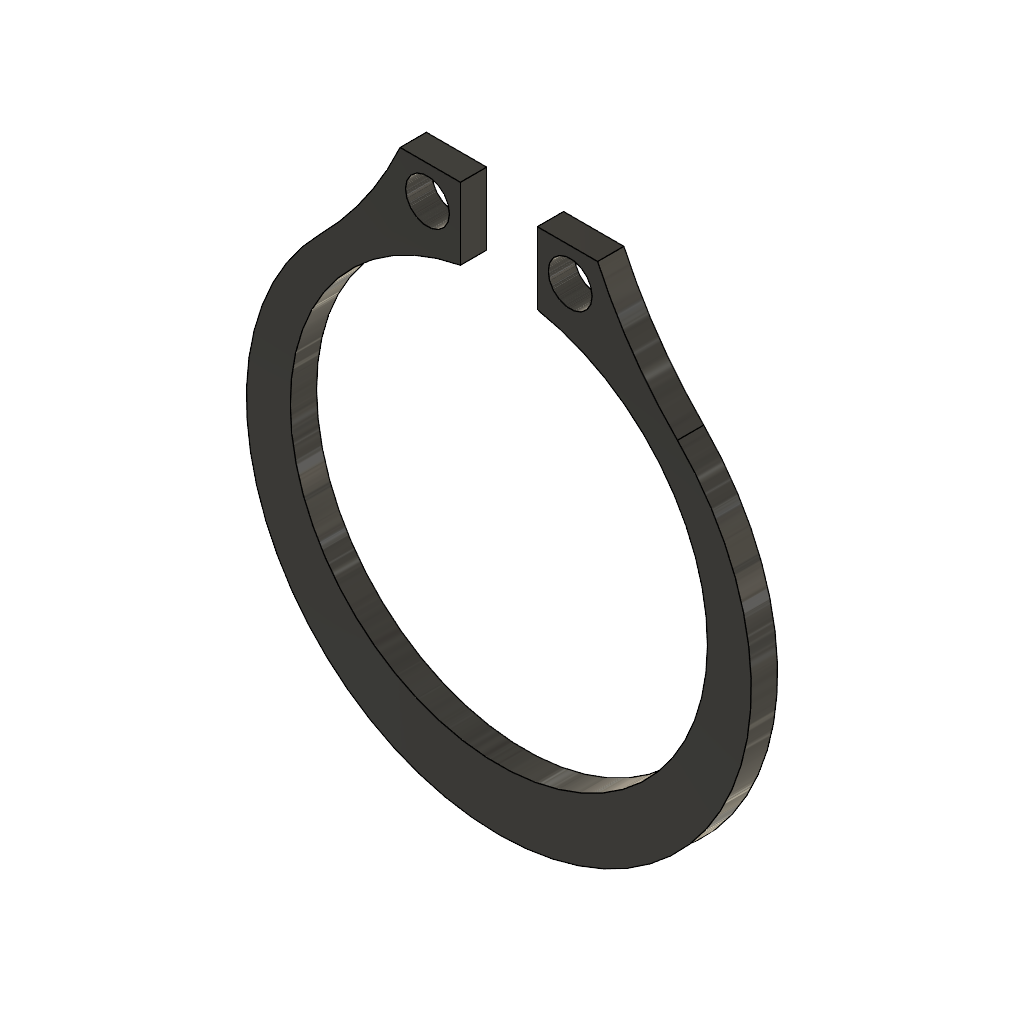
two_stage_reduction_v2 (Autodesk Fusion 360 archive; units mm, degrees)
design "counter_retaining_ring"
part number: 2026-10-06-01-37-24-822
Autodesk Fusion 360 part; units mm, degrees
sketch "Sketch1" plane through (0, 0, 0) normal (0, 1, 0) x (1, 0, 0)
  line L0 (0, 0) -> (0, -16.4292)
  line L1 (-1.75, -12.613) -> (-1.75, -9.3374)
  line L2 (-1.75, -12.613) -> (-4.5, -12.613)
  arc A0 (-4.5, -12.613) -> (-8.1353, -7.3782) centre (-20.8688, -20.1005) ccw
  arc A1 (8.1353, -7.3782) -> (4.5, -12.613) centre (20.8688, -20.1005) ccw
  line L3 (1.75, -12.613) -> (4.5, -12.613)
  line L4 (1.75, -12.613) -> (1.75, -9.3374)
  arc A2 (8.1353, -7.3782) -> (-8.1353, -7.3782) centre (0, 0.75) ccw
  arc A3 (1.75, -9.3374) -> (-1.75, -9.3374) centre (0, 0) ccw
  dimension "d1" = 19
  dimension "d2" = 0.75
  dimension "d3" = 23
  dimension "d5" = 3.5
  dimension "d6" = 9
  dimension "d7" = 18
  constraint coincident L0.start A3.centre
  constraint vertical L0
  constraint vertical L1
  constraint perpendicular L1 L2
  constraint tangent A0 A2
  constraint symmetric L0 L1.start L3.start
  constraint symmetric L0 L1.end L4.end
  constraint symmetric L0 L2.end A1.end
  constraint symmetric L0 A0.end A1.start
  constraint symmetric L0 A0 A1
  measures "d1" diameter of A3
  measures "d2" distance of L0.start A2.centre
  measures "d3" diameter of A2
  measures "d6" distance of L2.end A1.end
  measures "d7" radius of A0
extrude "Extrude1" add sketch "Sketch1" along normal blind 1.2
sketch "Sketch2" plane through (0, 0, 0) normal (0, 1, 0) x (1, 0, 0)
  circle A0 centre (-3.25, -11.113) radius 1
  line L0 (-1.75, -12.613) -> (-4.5, -12.613)
  line L1 (-1.75, -12.613) -> (-1.75, -9.3374)
  line L2 (0, -13.9274) -> (0, 0)
  circle A1 centre (3.25, -11.113) radius 1
  dimension "d10" = 2
  dimension "d11" = 1.5
  dimension "d12" = 1.5
  constraint coincident L2.end origin
  constraint vertical L2
  constraint symmetric A0 L2 A1
  measures "d10" diameter of A0
  measures "d11" distance of A0.centre L0
  measures "d12" distance of A0.centre L1
extrude "Extrude2" cut sketch "Sketch2" along normal blind 1.2

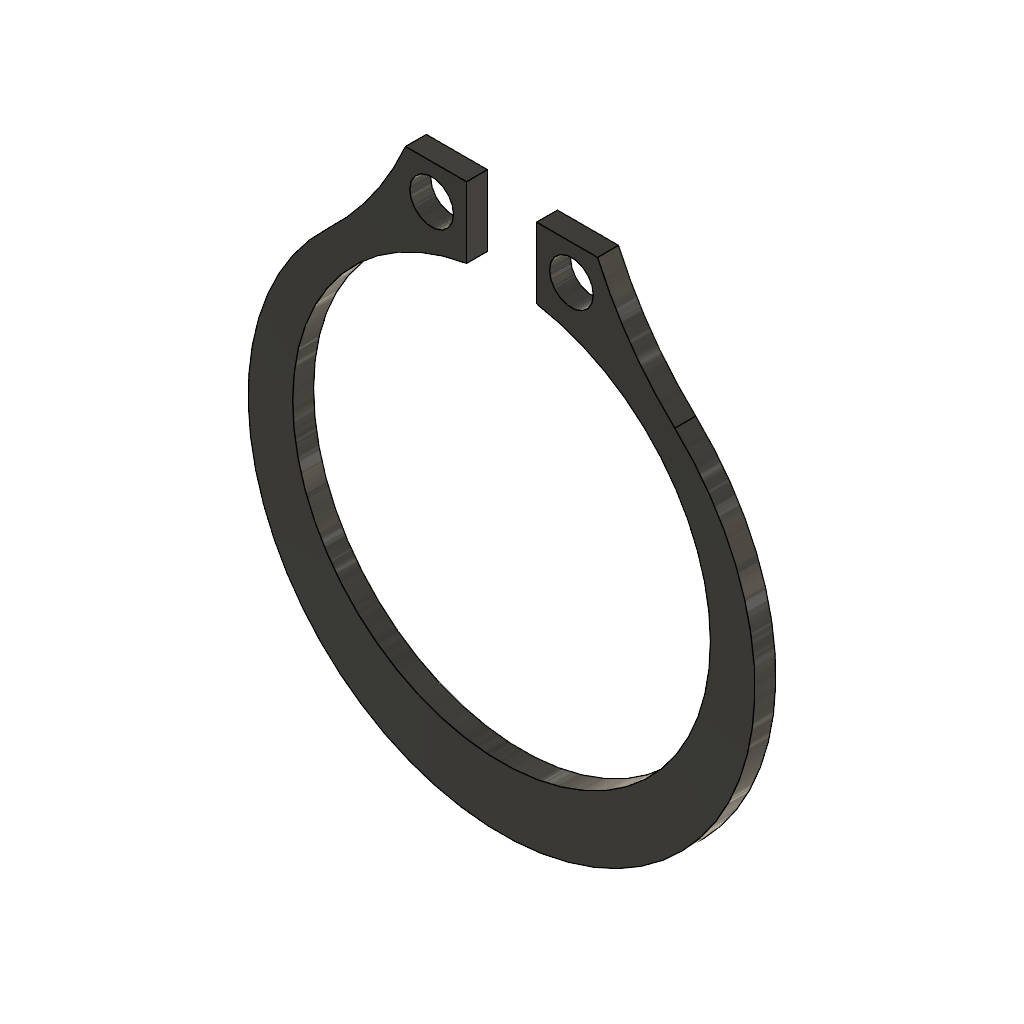
design "output_retaining_ring"
part number: 2026-10-06-01-58-45-962
Autodesk Fusion 360 part; units mm, degrees
sketch "Sketch1" plane through (0, 0, 0) normal (0, 1, 0) x (1, 0, 0)
  line L0 (0, 0) -> (0, -25)
  line L1 (-2, -15.834) -> (-2, -11.7814)
  line L2 (-2, -15.834) -> (-5.5, -15.834)
  arc A0 (-5.5, -15.834) -> (-9.9167, -9.5787) centre (-22.911, -23.4405) ccw
  arc A1 (9.9167, -9.5787) -> (5.5, -15.834) centre (22.911, -23.4405) ccw
  line L3 (2, -15.834) -> (5.5, -15.834)
  line L4 (2, -15.834) -> (2, -11.7814)
  arc A2 (9.9167, -9.5787) -> (-9.9167, -9.5787) centre (0, 1) ccw
  arc A3 (2, -11.7814) -> (-2, -11.7814) centre (0, 0) ccw
  dimension "d1" = 23.9
  dimension "d2" = 29
  dimension "d3" = 1
  dimension "d4" = 4
  dimension "d6" = 11
  dimension "d7" = 19
  constraint coincident L0.start A3.centre
  constraint vertical L0
  constraint vertical L1
  constraint perpendicular L1 L2
  constraint tangent A0 A2
  constraint symmetric L0 L1.start L3.start
  constraint symmetric L0 L1.end L4.end
  constraint symmetric L0 L2.end A1.end
  constraint symmetric L0 A0.end A1.start
  constraint symmetric L0 A0 A1
  measures "d1" diameter of A3
  measures "d2" diameter of A2
  measures "d3" distance of L0.start A2.centre
  measures "d6" distance of L2.end A1.end
  measures "d7" radius of A0
extrude "Extrude1" add sketch "Sketch1" along normal blind 1.2
sketch "Sketch2" plane through (0, 0, 0) normal (0, 1, 0) x (1, 0, 0)
  circle A0 centre (-4, -13.834) radius 1.25
  line L0 (-2, -15.834) -> (-5.5, -15.834)
  line L1 (-2, -15.834) -> (-2, -11.7814)
  line L2 (0, -17.5) -> (0, 0)
  circle A1 centre (4, -13.834) radius 1.25
  dimension "d10" = 2.5
  dimension "d11" = 2
  dimension "d12" = 2
  constraint coincident L2.end origin
  constraint vertical L2
  constraint symmetric A0 L2 A1
  measures "d10" diameter of A0
  measures "d11" distance of A0.centre L0
  measures "d12" distance of A0.centre L1
extrude "Extrude2" cut sketch "Sketch2" along normal blind 1.2

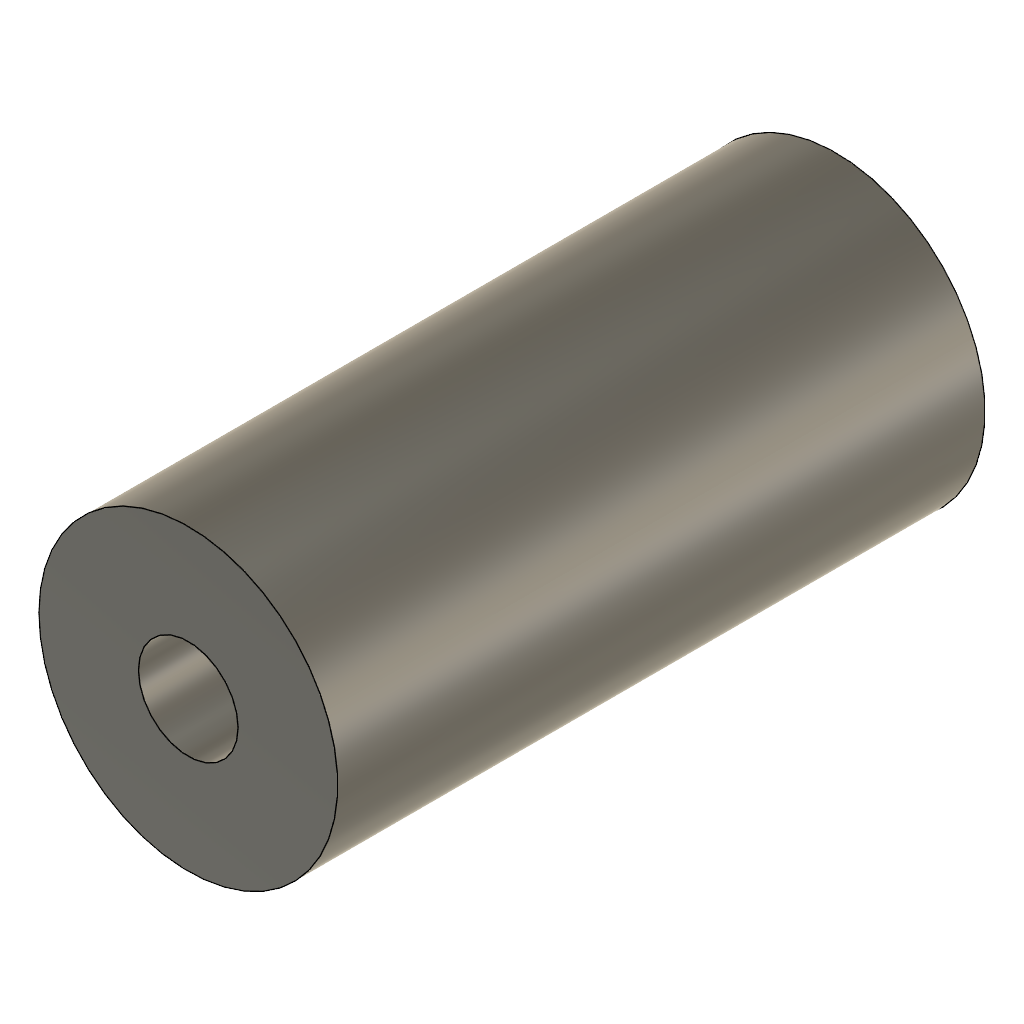
design "input_gearspacer"
part number: 2026-10-07-02-27-22-162
Autodesk Fusion 360 part; units mm, degrees
sketch "Sketch1" plane through (0, 0, 0) normal (0, 1, 0) x (1, 0, 0)
  circle A0 centre (0, 0) radius 5
  circle A1 centre (0, 0) radius 15
  dimension "d1" = 10
  dimension "d2" = 30
  constraint coincident A0.centre A1.centre
  constraint concentric A0 A1
  measures "d1" diameter of A0
  measures "d2" diameter of A1
extrude "Extrude1" add sketch "Sketch1" along normal blind 65

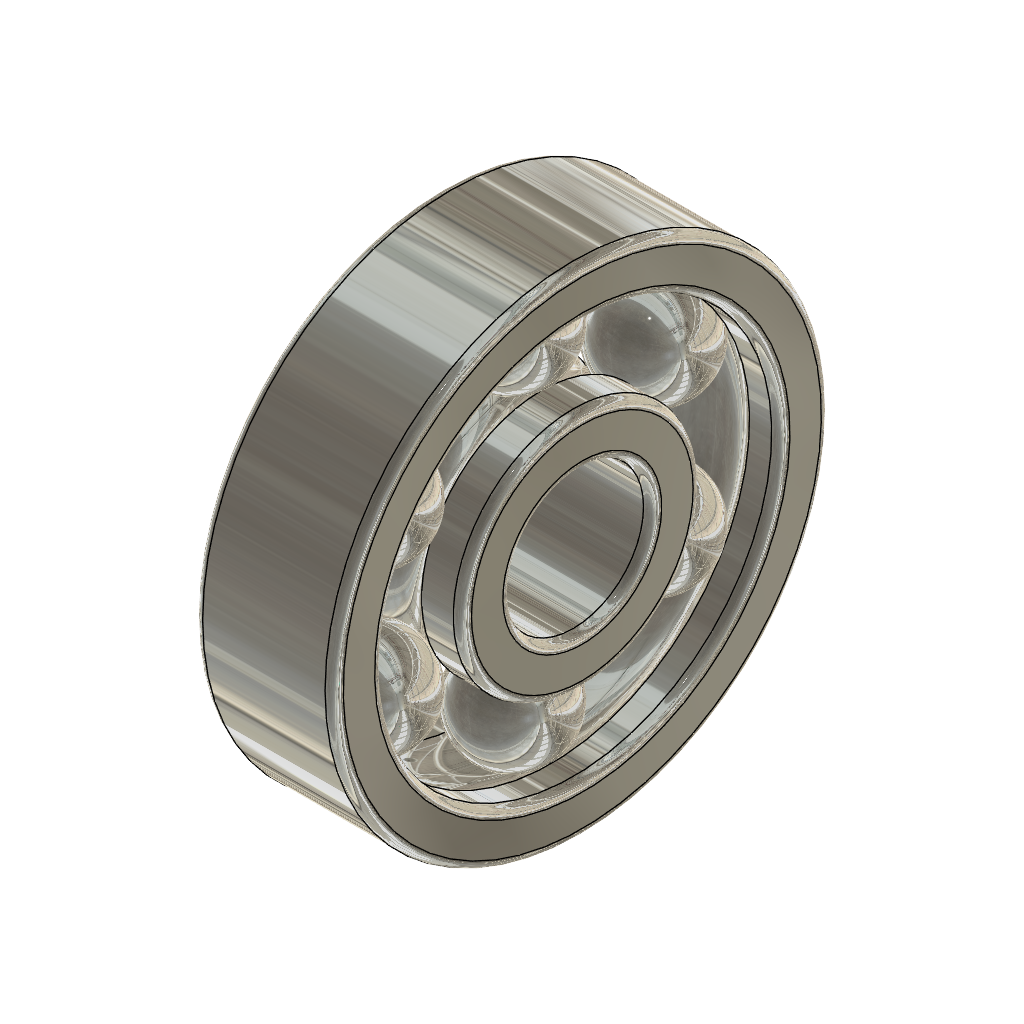
design "input_bearing"
part number: 2026-10-06-00-42-18-262
Autodesk Fusion 360 part; units mm, degrees
sketch "Sketch1" plane through (0, 0, 0) normal (0, 1, 0) x (1, 0, 0)
  line L0 (-8.5, -30) -> (8.5, -30)
  line L1 (8.5, -30) -> (8.5, -24)
  line L2 (-8.5, -24) -> (-8.5, -30)
  line L3 (8.5, -24) -> (4.7181, -24)
  line L4 (-4.7181, -24) -> (-8.5, -24)
  arc A0 (-4.7181, -24) -> (4.7181, -24) centre (0, -19.75) ccw
  dimension "d1" = 6
  dimension "d2" = 17
  dimension "d4" = 8.5
  dimension "d6" = 30
  dimension "d7" = 12.7
  dimension "d9" = 19.75
  constraint horizontal L0
  constraint vertical L1
  constraint horizontal L3
  constraint vertical L2
  constraint vertical origin A0.centre
  constraint collinear L3 L4
  measures "d1" distance of L0.start L2.start
  measures "d2" distance of L0.start L0.end
  measures "d4" distance of origin L1
  measures "d6" distance of origin L0
  measures "d7" diameter of A0
  measures "d9" distance of origin A0.centre
revolve "Revolve1" add sketch "Sketch1" angle 360 about axis through (1.75, 0, 0) along (1, 0, 0) makes body 1
sketch "Sketch2" plane through (0, 0, 0) normal (0, 1, 0) x (1, 0, 0)
  line L0 (8.5, -14.5) -> (8.5, -8.5)
  line L1 (8.5, -8.5) -> (-8.5, -8.5)
  line L2 (-8.5, -8.5) -> (-8.5, -14.5)
  arc A0 (3.5721, -14.5) -> (-3.5721, -14.5) centre (0, -19.75) ccw
  line L3 (-8.5, -14.5) -> (-3.5721, -14.5)
  line L4 (3.5721, -14.5) -> (8.5, -14.5)
  dimension "d13" = 17
  dimension "d14" = 6
  dimension "d15" = 8.5
  dimension "d16" = 12.7
  dimension "d17" = 19.75
  dimension "d29" = 8.5
  constraint horizontal L3
  constraint vertical L0
  constraint horizontal L1
  constraint vertical L2
  constraint collinear L3 L4
  measures "d13" distance of L2.end L0.start
  measures "d14" distance of L2.end L1.end
  measures "d15" distance of origin L0
  measures "d16" diameter of A0
  measures "d17" distance of origin A0.centre
  measures "d29" distance of origin L1
revolve "Revolve2" add sketch "Sketch2" angle 360 about axis through (1.75, 0, 0) along (1, 0, 0) separate body makes body 2
fillet "Fillet3" radius 1.1 4 faces at (-8.5, 1.4904, 27.8883) (8.5, 2.6828, 27.799) (8.5, 1.1427, 12.4144) (-8.5, 0.7204, 12.446) on bodies 1 2
sketch "Sketch3" plane through (0, 0, 0) normal (1, 0, 0) x (0, 1, 0)
  line L0 (0, 26.1) -> (0, 13.4)
  arc A0 (0, 26.1) -> (0, 13.4) centre (0, 19.75) ccw
  dimension "d23" = 12.7
  dimension "d25" = 19.75
  constraint perpendicular L0 A0
  measures "d23" diameter of A0
  measures "d25" distance of origin A0.centre
revolve "Revolve3" add sketch "Sketch3" angle 360 about axis through (0, 0, 26.1) along (0, 0, -1) separate body makes body 3
pattern_circular "C-Pattern1" count 6 over 360 about axis through (1.75, 0, 0) along (1, 0, 0) of bodies 3 makes body 4 at (-1.501, -21.2843, 5.3369) makes body 5 at (-1.501, -15.264, -15.7643) makes body 6 at (-1.501, 6.0203, -21.1012) makes body 7 at (-1.501, 21.2843, -5.3369) makes body 8 at (-1.501, 15.264, 15.7643)

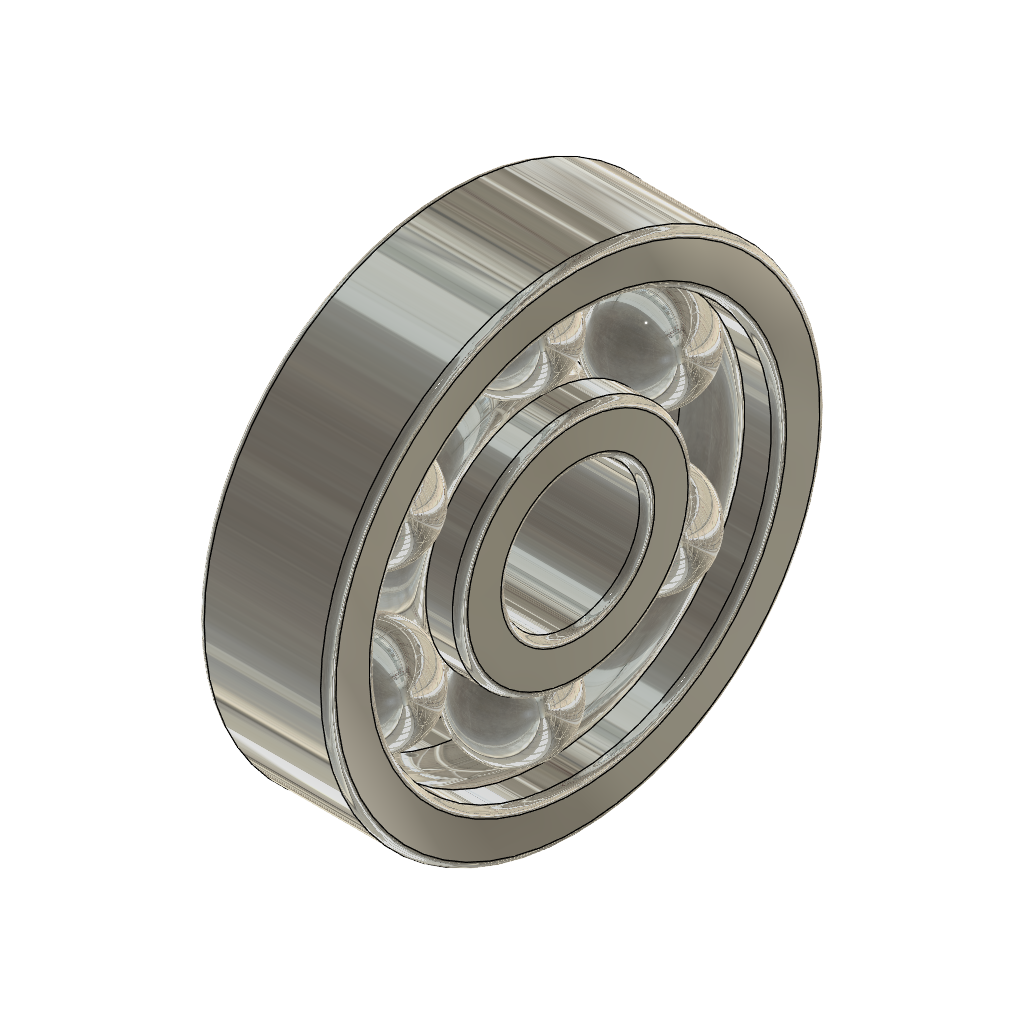
design "counter_bearing"
part number: 2026-10-06-02-07-17-765
Autodesk Fusion 360 part; units mm, degrees
sketch "Sketch1" plane through (0, 0, 0) normal (0, 1, 0) x (1, 0, 0)
  line L0 (-9.5, -29) -> (-9.5, -36)
  line L1 (-9.5, -36) -> (9.5, -36)
  line L2 (9.5, -36) -> (9.5, -29)
  line L3 (9.5, -29) -> (4.5622, -29)
  line L4 (-4.5622, -29) -> (-9.5, -29)
  arc A0 (-4.5622, -29) -> (4.5622, -29) centre (0, -23) ccw
  dimension "d1" = 19
  dimension "d2" = 7
  dimension "d4" = 9.5
  dimension "d5" = 36
  dimension "d6" = 15.075
  dimension "d7" = 23
  constraint horizontal L3
  constraint vertical L0
  constraint horizontal L1
  constraint vertical L2
  constraint collinear L3 L4
  measures "d1" distance of L2.end L0.start
  measures "d2" distance of L2.end L1.end
  measures "d4" distance of origin L0
  measures "d5" distance of origin L1
  measures "d6" diameter of A0
  measures "d7" distance of origin A0.centre
revolve "Revolve1" add sketch "Sketch1" angle 360 about axis through (1.75, 0, 0) along (1, 0, 0) makes body 1
sketch "Sketch2" plane through (0, 0, 0) normal (0, 1, 0) x (1, 0, 0)
  line L0 (9.5, -17) -> (9.5, -10)
  line L1 (9.5, -10) -> (-9.5, -10)
  line L2 (-9.5, -10) -> (-9.5, -17)
  line L3 (-9.5, -17) -> (-4.5622, -17)
  line L4 (4.5622, -17) -> (9.5, -17)
  arc A0 (4.5622, -17) -> (-4.5622, -17) centre (0, -23) ccw
  dimension "d9" = 19
  dimension "d10" = 7
  dimension "d11" = 9.5
  dimension "d12" = 15.075
  dimension "d13" = 23
  dimension "d14" = 10
  constraint horizontal L3
  constraint vertical L0
  constraint horizontal L1
  constraint vertical L2
  constraint collinear L3 L4
  measures "d9" distance of L2.end L0.start
  measures "d10" distance of L2.end L1.end
  measures "d11" distance of origin L0
  measures "d12" diameter of A0
  measures "d13" distance of origin A0.centre
  measures "d14" distance of origin L1
revolve "Revolve2" add sketch "Sketch2" angle 360 about axis through (1.75, 0, 0) along (1, 0, 0) separate body makes body 2
fillet "Fillet1" radius 1.1 4 faces at (9.5, 1.7885, 33.5326) (-9.5, 1.7885, 33.5326) (9.5, 1.3414, 14.5661) (-9.5, 0.8446, 14.6034) on bodies 1 2
sketch "Sketch3" plane through (0, 0, 0) normal (1, 0, 0) x (0, 1, 0)
  line L0 (0, 30.5375) -> (0, 15.4625)
  arc A0 (0, 30.5375) -> (0, 15.4625) centre (0, 23) ccw
  dimension "d18" = 15.075
  dimension "d19" = 23
  constraint vertical origin A0.centre
  constraint perpendicular L0 A0
  measures "d18" diameter of A0
  measures "d19" distance of origin A0.centre
revolve "Revolve3" add sketch "Sketch3" angle 360 about axis through (0, 0, 30.5375) along (0, 0, -1) separate body makes body 3
pattern_circular "C-Pattern1" count 6 over 360 about axis through (1.75, 0, 0) along (1, 0, 0) of bodies 3 makes body 4 at (-1.7817, -24.8806, 6.1132) makes body 5 at (-1.7817, -17.7345, -18.4907) makes body 6 at (-1.7817, 7.1461, -24.6039) makes body 7 at (-1.7817, 24.8806, -6.1132) makes body 8 at (-1.7817, 17.7345, 18.4907)

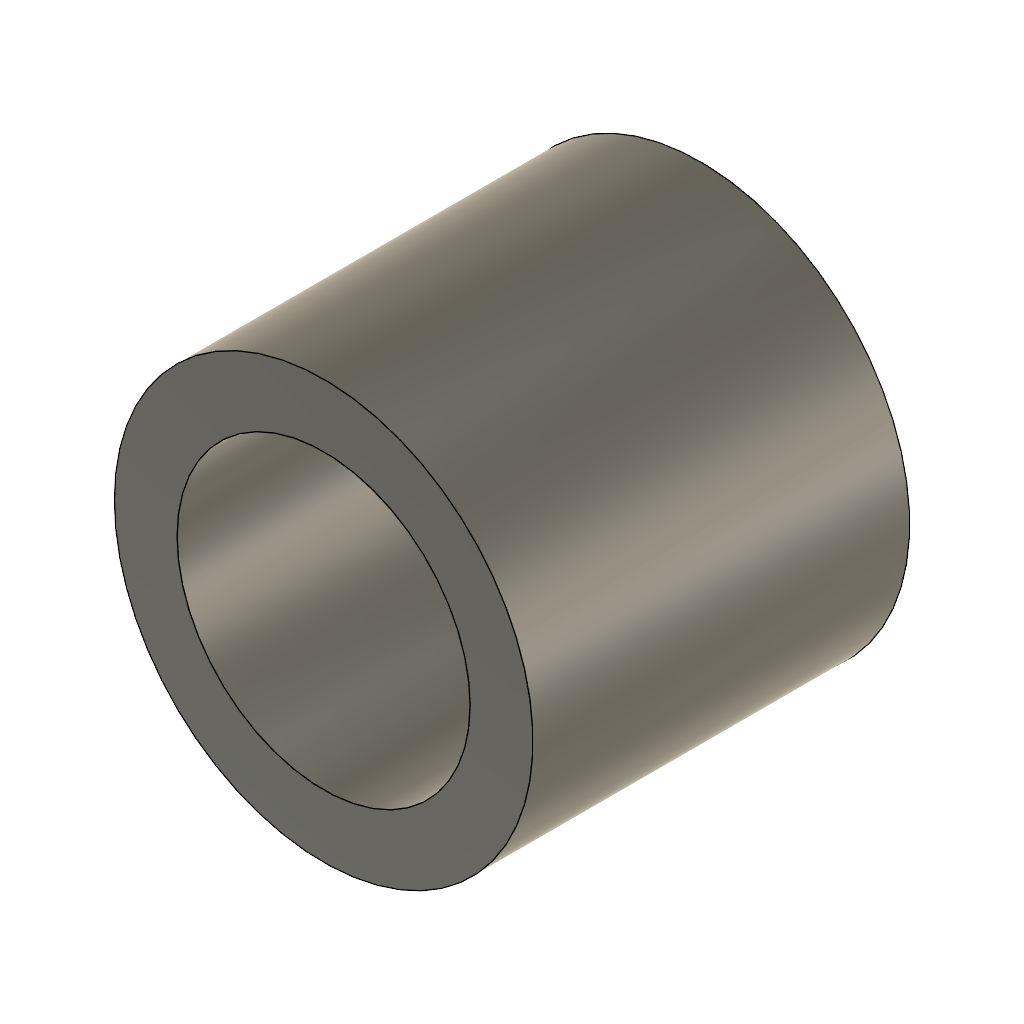
design "output_spacer"
part number: 2026-10-07-02-44-27-604
Autodesk Fusion 360 part; units mm, degrees
sketch "Sketch1" plane through (0, 0, 0) normal (0, 1, 0) x (1, 0, 0)
  circle A0 centre (0, 0) radius 17.5
  circle A1 centre (0, 0) radius 25
  dimension "d1" = 35
  dimension "d2" = 50
  constraint coincident A0.centre A1.centre
  measures "d1" diameter of A0
  measures "d2" diameter of A1
extrude "Extrude1" add sketch "Sketch1" along normal blind 45

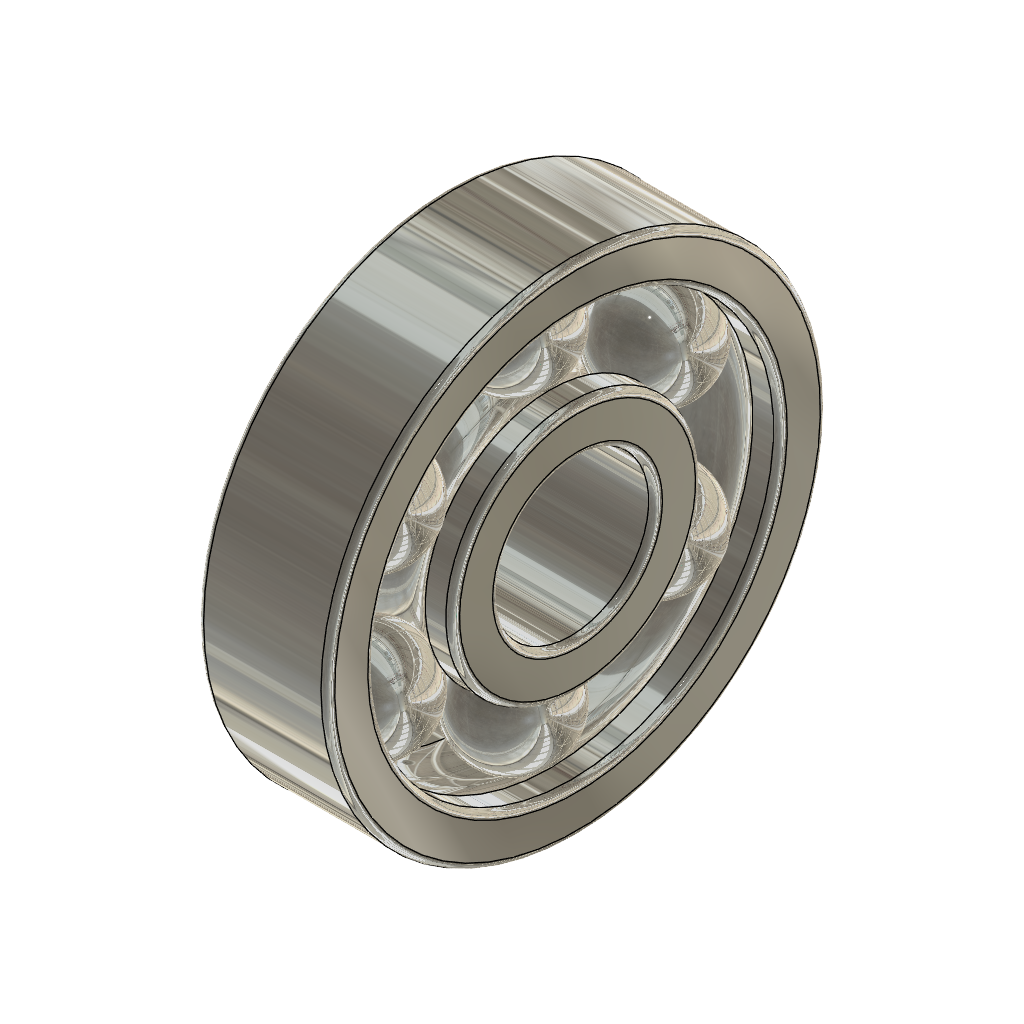
design "output_bearing"
part number: 2026-10-06-02-27-55-764
Autodesk Fusion 360 part; units mm, degrees
sketch "Sketch1" plane through (0, 0, 0) normal (0, 1, 0) x (1, 0, 0)
  line L0 (-10.5, -40) -> (10.5, -40)
  line L1 (10.5, -40) -> (10.5, -32.5)
  line L2 (-10.5, -32.5) -> (-10.5, -40)
  line L3 (10.5, -32.5) -> (6.0965, -32.5)
  line L4 (-6.0965, -32.5) -> (-10.5, -32.5)
  arc A0 (-6.0965, -32.5) -> (6.0965, -32.5) centre (0, -26.25) ccw
  dimension "d1" = 21
  dimension "d2" = 7.5
  dimension "d3" = 10.5
  dimension "d4" = 40
  dimension "d5" = 17.462
  dimension "d6" = 26.25
  constraint horizontal L0
  constraint vertical L1
  constraint horizontal L3
  constraint vertical L2
  constraint collinear L3 L4
  measures "d1" distance of L0.start L0.end
  measures "d2" distance of L0.start L2.start
  measures "d3" distance of origin L2
  measures "d4" distance of origin L0
  measures "d5" diameter of A0
  measures "d6" distance of origin A0.centre
revolve "Revolve1" add sketch "Sketch1" angle 360 about axis through (1.75, 0, 0) along (1, 0, 0) makes body 1
sketch "Sketch2" plane through (0, 0, 0) normal (0, 1, 0) x (1, 0, 0)
  line L0 (10.5, -20) -> (10.5, -12.5)
  line L1 (10.5, -12.5) -> (-10.5, -12.5)
  line L2 (-10.5, -12.5) -> (-10.5, -20)
  arc A0 (6.0965, -20) -> (-6.0965, -20) centre (0, -26.25) ccw
  line L3 (-10.5, -20) -> (-6.0965, -20)
  line L4 (6.0965, -20) -> (10.5, -20)
  dimension "d8" = 21
  dimension "d9" = 7.5
  dimension "d10" = 10.5
  dimension "d11" = 12.5
  dimension "d12" = 17.462
  dimension "d13" = 26.25
  constraint horizontal L3
  constraint vertical L0
  constraint horizontal L1
  constraint vertical L2
  constraint vertical origin A0.centre
  constraint collinear L3 L4
  measures "d8" distance of L2.end L0.start
  measures "d9" distance of L2.end L1.end
  measures "d10" distance of origin L0
  measures "d11" distance of origin L1
  measures "d12" diameter of A0
  measures "d13" distance of origin A0.centre
revolve "Revolve2" add sketch "Sketch2" angle 360 about axis through (1.75, 0, 0) along (1, 0, 0) separate body makes body 2
fillet "Fillet1" radius 1.1 4 faces at (10.5, 3.6019, 37.2301) (-10.5, 1.9872, 37.3511) (10.5, 1.6146, 17.379) (-10.5, 1.6146, 17.379) on bodies 1 2
sketch "Sketch3" plane through (0, 0, 0) normal (1, 0, 0) x (0, 1, 0)
  line L0 (0, 34.981) -> (0, 17.519)
  arc A0 (0, 34.981) -> (0, 17.519) centre (0, 26.25) ccw
  dimension "d17" = 17.462
  dimension "d18" = 26.25
  constraint vertical origin A0.centre
  constraint perpendicular L0 A0
  measures "d17" diameter of A0
  measures "d18" distance of origin A0.centre
revolve "Revolve3" add sketch "Sketch3" angle 360 about axis through (0, 0, 34.981) along (0, 0, -1) separate body makes body 3
pattern_circular "C-Pattern1" count 6 over 360 about axis through (1.75, 0, 0) along (1, 0, 0) of bodies 3 makes body 4 at (-2.0638, -28.4809, 6.8853) makes body 5 at (-2.0638, -20.2033, -21.2226) makes body 6 at (-2.0638, 8.2776, -28.1078) makes body 7 at (-2.0638, 28.4809, -6.8853) makes body 8 at (2.0638, 20.2033, 21.2226)

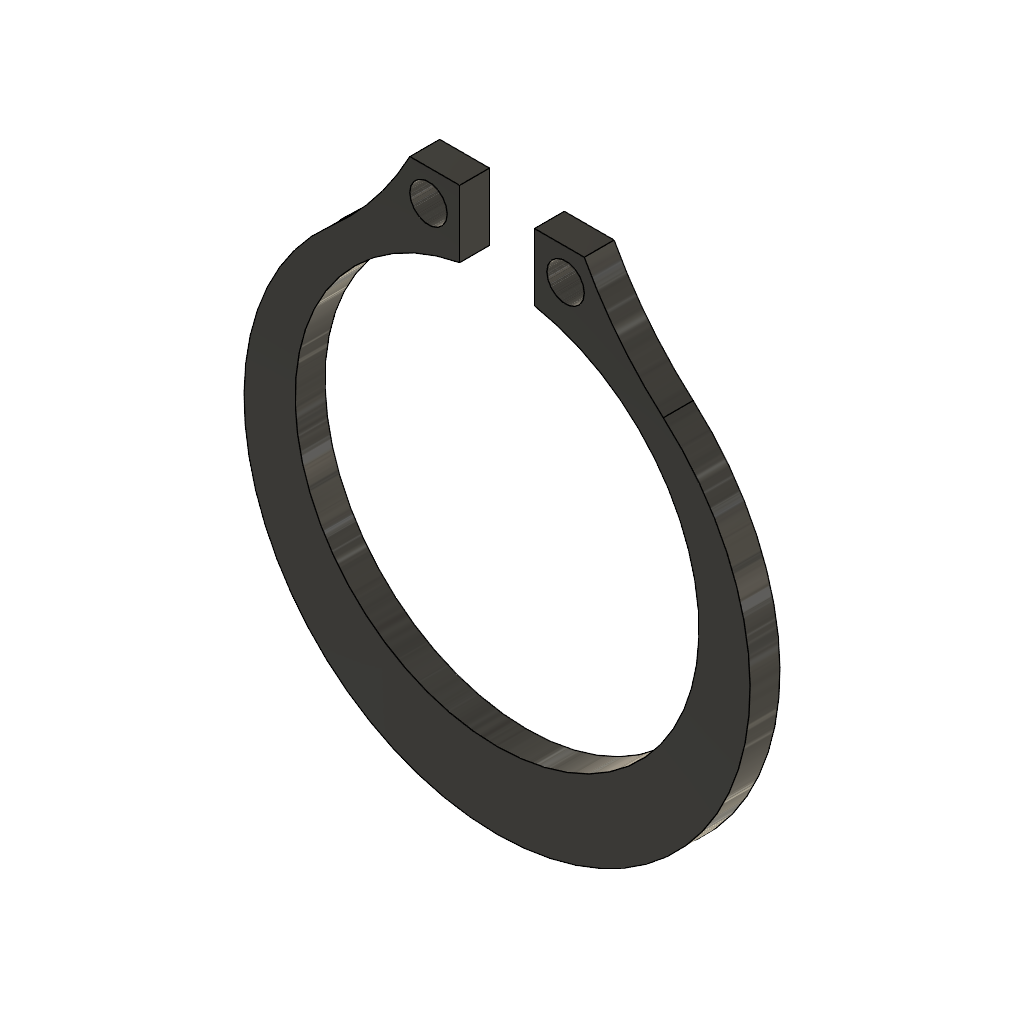
design "input_retaining_ring"
part number: 2026-10-06-01-21-28-079
Autodesk Fusion 360 part; units mm, degrees
sketch "Sketch1" plane through (0, 0, 0) normal (0, 1, 0) x (1, 0, 0)
  line L0 (0, 0) -> (0, -15)
  line L1 (1.5, -10.6492) -> (1.5, -7.9599)
  line L2 (1.5, -10.6492) -> (3.5, -10.6492)
  arc A0 (6.6701, -6.656) -> (3.5, -10.6492) centre (15.8666, -17.2117) ccw
  line L3 (-1.5, -10.6492) -> (-3.5, -10.6492)
  line L4 (-1.5, -10.6492) -> (-1.5, -7.9599)
  arc A1 (-3.5, -10.6492) -> (-6.6701, -6.656) centre (-15.8666, -17.2117) ccw
  arc A2 (1.5, -7.9599) -> (-1.5, -7.9599) centre (0, 0) ccw
  arc A3 (6.6701, -6.656) -> (-6.6701, -6.656) centre (0, 1) ccw
  dimension "d13" = 16.2
  dimension "d15" = 1
  dimension "d16" = 3
  dimension "d17" = 7
  dimension "d27" = 14
  constraint coincident L0.start A2.centre
  constraint vertical L0
  constraint vertical L1
  constraint perpendicular L1 L2
  constraint tangent A0 A3
  constraint symmetric L0 L1.start L3.start
  constraint symmetric L0 L1.end L4.end
  constraint symmetric L0 L2.end L3.end
  constraint symmetric L0 A0.start A1.end
  constraint symmetric L0 A0 A1
  measures "d13" diameter of A2
  measures "d15" distance of L0.start A3.centre
  measures "d17" distance of L2.end L3.end
  measures "d27" radius of A1
extrude "Extrude2" add sketch "Sketch1" along normal blind 1.2
sketch "Sketch2" plane through (0, 0, 0) normal (0, 1, 0) x (1, 0, 0)
  line L0 (0, 0) -> (0, -12) construction
  circle A0 centre (2.75, -9.3992) radius 0.75
  line L1 (1.5, -10.6492) -> (1.5, -7.9599)
  line L2 (1.5, -10.6492) -> (3.5, -10.6492)
  line L3 (0, 0) -> (0, -15)
  circle A1 centre (-2.75, -9.3992) radius 0.75
  dimension "d23" = 1.25
  dimension "d24" = 1.25
  dimension "d28" = 1.5
  constraint coincident L0.start L3.start
  constraint vertical L0
  constraint symmetric A0 L3 A1
  measures "d23" distance of A0.centre L1
  measures "d24" distance of A0.centre L2
  measures "d28" diameter of A0
extrude "Extrude3" cut sketch "Sketch2" along normal blind 1.2

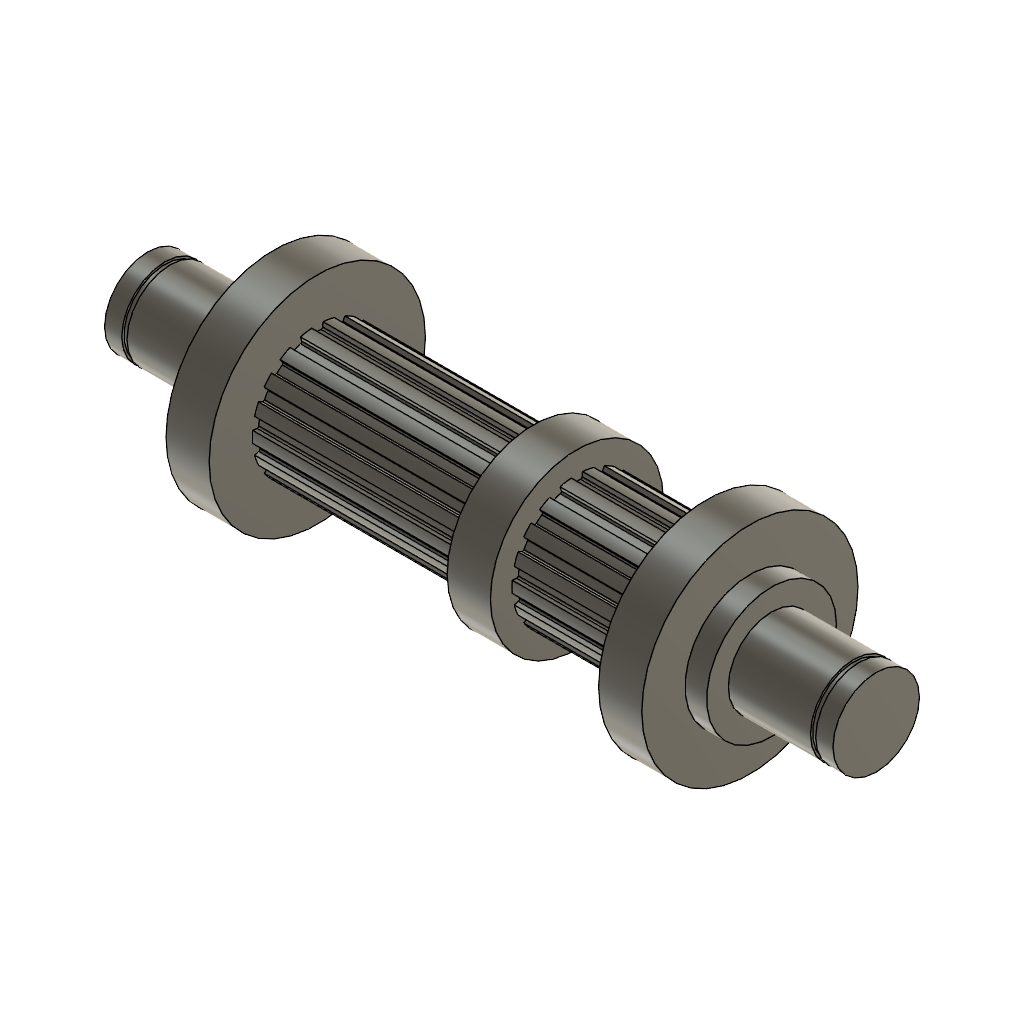
design "counter_shaft"
part number: 2026-10-05-13-03-48-903
Autodesk Fusion 360 part; units mm, degrees
sketch "Sketch1" plane through (0, 0, 0) normal (0, 0, 1) x (1, 0, 0)
  line L0 (0, 0) -> (0, 10)
  line L1 (29.2, 25) -> (39.2, 25)
  line L2 (39.2, 25) -> (39.2, 15)
  line L3 (39.2, 15) -> (89.2, 15)
  line L4 (89.2, 15) -> (89.2, 20)
  line L5 (89.2, 20) -> (99.2, 20)
  line L6 (99.2, 20) -> (99.2, 15)
  line L7 (99.2, 15) -> (129.2, 15)
  line L8 (0, 10) -> (4, 10)
  line L9 (4, 10) -> (4, 9.5)
  line L10 (4, 9.5) -> (5.2, 9.5)
  line L11 (5.2, 9.5) -> (5.2, 10)
  line L12 (5.2, 10) -> (24.2, 10)
  line L13 (129.2, 15) -> (129.2, 25)
  line L14 (129.2, 25) -> (139.2, 25)
  line L15 (139.2, 25) -> (139.2, 15)
  line L16 (24.2, 10) -> (24.2, 15)
  line L17 (24.2, 15) -> (29.2, 15)
  line L18 (29.2, 15) -> (29.2, 25)
  line L19 (153, 0) -> (-15, 0) construction
  line L20 (139.2, 15) -> (144.2, 15)
  line L21 (144.2, 15) -> (144.2, 10)
  line L22 (144.2, 10) -> (163.2, 10)
  line L23 (163.2, 10) -> (163.2, 9.5)
  line L24 (163.2, 9.5) -> (164.4, 9.5)
  line L25 (164.4, 9.5) -> (164.4, 10)
  line L26 (164.4, 10) -> (168.4, 10)
  line L27 (168.4, 10) -> (168.4, 0)
  line L28 (0, 0) -> (168.4, 0)
  dimension "d2" = 4
  dimension "d3" = 1.2
  dimension "d8" = 10
  dimension "d25" = 19
  dimension "d27" = 50
  dimension "d28" = 30
  dimension "d29" = 10
  dimension "d30" = 10
  dimension "d50" = 5
  dimension "d51" = 10
  dimension "d52" = 15
  dimension "d53" = 25
  dimension "d54" = 15
  dimension "d55" = 20
  dimension "d56" = 25
  dimension "d57" = 5
  dimension "d58" = 19
  dimension "d59" = 15
  dimension "d60" = 10
  dimension "d61" = 1.2
  dimension "d63" = 4
  dimension "d64" = 9.5
  dimension "d65" = 9.5
  dimension "d67" = 70
  dimension "d70" = 120
  constraint coincident L0.start L28.start
  constraint vertical L0
  constraint perpendicular L1 L2
  constraint perpendicular L2 L3
  constraint perpendicular L3 L4
  constraint perpendicular L4 L5
  constraint perpendicular L5 L6
  constraint perpendicular L6 L7
  constraint perpendicular L0 L8
  constraint perpendicular L8 L9
  constraint perpendicular L9 L10
  constraint perpendicular L10 L11
  constraint perpendicular L11 L12
  constraint collinear L8 L12
  constraint perpendicular L7 L13
  constraint perpendicular L13 L14
  constraint perpendicular L14 L15
  constraint collinear L3 L7
  constraint perpendicular L12 L16
  constraint perpendicular L16 L17
  constraint perpendicular L17 L18
  constraint parallel L7 L19
  constraint perpendicular L15 L20
  constraint perpendicular L14 L21
  constraint perpendicular L21 L22
  constraint perpendicular L22 L23
  constraint perpendicular L23 L24
  constraint perpendicular L24 L25
  constraint perpendicular L25 L26
  constraint coincident L19 L27.end
  constraint perpendicular L19 L27
  constraint perpendicular L27 L28
  measures "d2" distance of L0.end L8.end
  measures "d3" distance of L9.end L10.end
  measures "d8" distance of L1.end L1.start
  measures "d25" distance of L12.end L11.end
  measures "d27" distance of L2.end L3.end
  measures "d28" distance of L6.end L7.end
  measures "d29" distance of L4.end L5.end
  measures "d30" distance of L13.end L14.end
  measures "d50" distance of L16.end L17.end
  measures "d51" distance of L12 L19
  measures "d52" distance of L17 L19
  measures "d53" distance of L1 L19
  measures "d54" distance of L3 L19
  measures "d55" distance of L5 L19
  measures "d56" distance of L14 L19
  measures "d57" distance of L15.end L20.end
  measures "d58" distance of L21.end L22.end
  measures "d59" distance of L19 L20
  measures "d60" distance of L19 L22
  measures "d61" distance of L23.end L24.end
  measures "d63" distance of L25.end L26.end
  measures "d64" distance of L19 L24
  measures "d65" distance of L10 L19
  measures "d67" distance of L6.end L17.end
  measures "d70" distance of L16.end L20.end
revolve "Revolve1" add sketch "Sketch1" angle 360 about axis through (130.4, 0, 0) along (-1, 0, 0)
ref_plane "WorkPlane1" through (39.2, 0, 0) normal (1, 0, 0) x (0, 0, -1)
sketch "Sketch2" plane through (39.2, 0, 0) normal (1, 0, 0) x (0, 1, 0)
  line L0 (0, 0) -> (0, 22) construction
  line L1 (1.2198, 13.9424) -> (1.3073, 14.9429)
  line L2 (-1.2198, 13.9424) -> (-1.3073, 14.9429)
  arc A0 (0.8494, 13.6235) -> (-0.8494, 13.6235) centre (0, 0) ccw
  arc A1 (1.3073, 14.9429) -> (-1.3073, 14.9429) centre (0, 0) ccw
  arc A2 (0.8494, 13.6235) -> (1.2198, 13.9424) centre (0.8711, 13.9729) ccw
  arc A3 (-1.2198, 13.9424) -> (-0.8494, 13.6235) centre (-0.8711, 13.9729) ccw
  dimension "d73" = 30
  dimension "d74" = 27.3
  dimension "d75" = 5
  dimension "d76" = 0.35
  constraint coincident L0.start A0.centre
  constraint vertical L0
  constraint symmetric L0 L1.end L2.end
  constraint tangent L1 A2
  constraint tangent A0 A2
  constraint tangent L2 A3
  constraint tangent A0 A3
  constraint equal A2 A3
  measures "d73" diameter of A1
  measures "d74" diameter of A0
  measures "d75" angle of L0 L1
  measures "d76" radius of A2
ref_plane "WorkPlane2" through (99.2, 0, 0) normal (1, 0, 0) x (0, 0, -1)
sketch "Sketch3" plane through (99.2, 0, 0) normal (1, 0, 0) x (0, 1, 0)
  line L0 (1.2198, 13.9424) -> (1.3073, 14.9429)
  arc A0 (0.8494, 13.6235) -> (1.2198, 13.9424) centre (0.8711, 13.9729) ccw
  arc A1 (0.8494, 13.6235) -> (-0.8494, 13.6235) centre (0, 0) ccw
  arc A2 (-1.2198, 13.9424) -> (-0.8494, 13.6235) centre (-0.8711, 13.9729) ccw
  line L1 (-1.2198, 13.9424) -> (-1.3073, 14.9429)
  arc A3 (1.3073, 14.9429) -> (-1.3073, 14.9429) centre (0, 0) ccw
  dimension "d79" = 30
  dimension "d80" = 27.3
  dimension "d81" = 0.35
  constraint tangent L0 A0
  constraint tangent A0 A1
  constraint tangent A2 L1
  constraint tangent A1 A2
  constraint equal A0 A2
  measures "d79" diameter of A3
  measures "d80" diameter of A1
  measures "d81" radius of A0
extrude "Extrude1" cut sketch "Sketch3" along normal blind 30
pattern_circular "C-Pattern1" count 18 over 360 about axis through (144.2, 0, 0) along (1, 0, 0) of "Extrude1"
extrude "Extrude2" cut sketch "Sketch2" along normal blind 50
pattern_circular "C-Pattern2" count 18 over 360 about axis through (89.2, 0, 0) along (1, 0, 0) of "Extrude2"

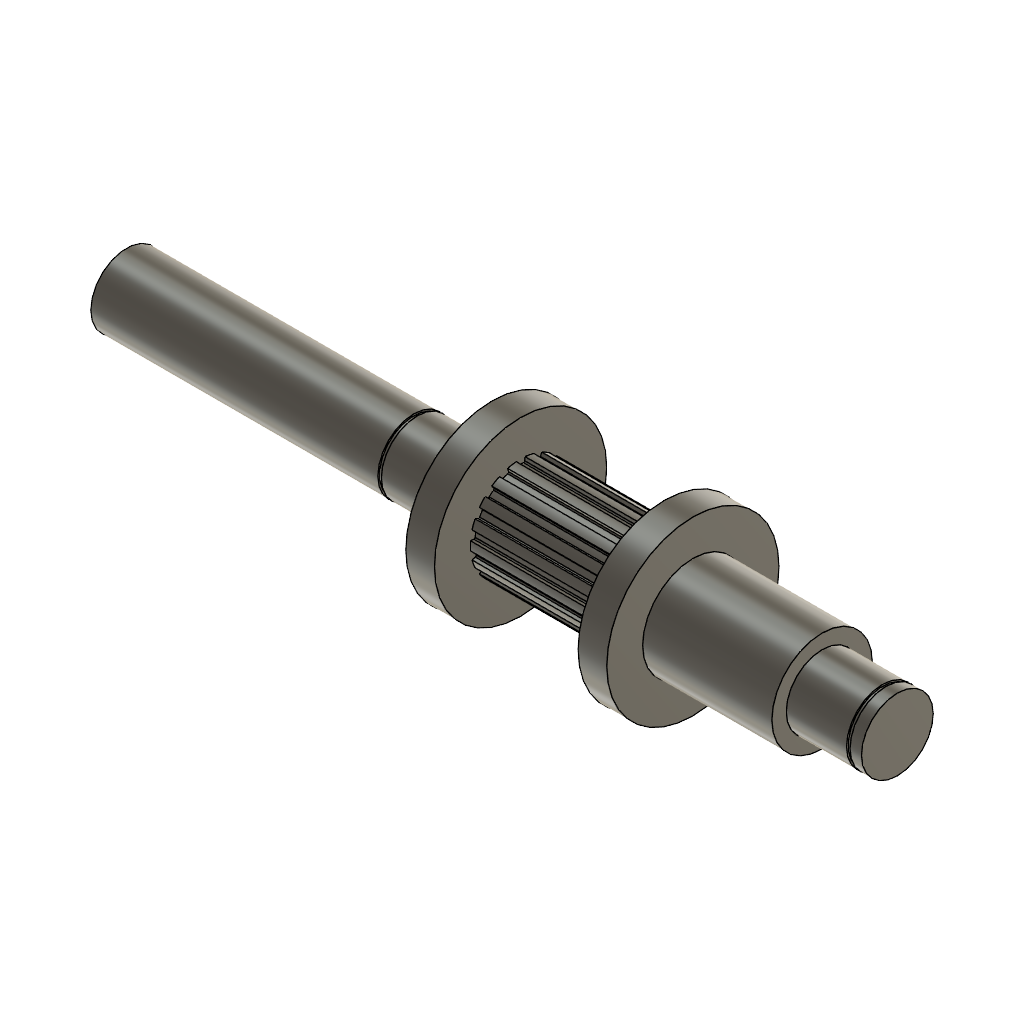
design "output_shaft"
part number: 2026-10-05-13-26-02-905
Autodesk Fusion 360 part; units mm, degrees
sketch "Sketch1" plane through (0, 0, 0) normal (0, 0, 1) x (1, 0, 0)
  line L0 (0, 0) -> (0, 12.5)
  line L1 (72.2, 12.5) -> (72.2, 17.5)
  line L2 (72.2, 17.5) -> (77.2, 17.5)
  line L3 (77.2, 17.5) -> (77.2, 30)
  line L4 (77.2, 30) -> (87.2, 30)
  line L5 (87.2, 30) -> (87.2, 17.5)
  line L6 (87.2, 17.5) -> (137.2, 17.5)
  line L7 (137.2, 17.5) -> (137.2, 30)
  line L8 (137.2, 30) -> (147.2, 30)
  line L9 (147.2, 30) -> (147.2, 17.5)
  line L10 (147.2, 17.5) -> (192.2, 17.5)
  line L11 (192.2, 17.5) -> (192.2, 12.5)
  line L12 (192.2, 12.5) -> (213.2, 12.5)
  line L13 (-8.1331, 0) -> (225, 0) construction
  line L14 (213.2, 12.5) -> (213.2, 11.95)
  line L15 (213.2, 11.95) -> (214.4, 11.95)
  line L16 (214.4, 11.95) -> (214.4, 12.5)
  line L17 (214.4, 12.5) -> (218.4, 12.5)
  line L18 (218.4, 12.5) -> (218.4, 0)
  line L19 (51.2, 12.5) -> (72.2, 12.5)
  line L20 (0, 12.5) -> (50, 12.5)
  line L21 (50, 12.5) -> (50, 11.95)
  line L22 (50, 11.95) -> (51.2, 11.95)
  line L23 (51.2, 11.95) -> (51.2, 12.5)
  line L24 (0, 0) -> (218.4, 0)
  dimension "d11" = 5
  dimension "d12" = 10
  dimension "d13" = 50
  dimension "d14" = 10
  dimension "d15" = 45
  dimension "d16" = 21
  dimension "d22" = 30
  dimension "d23" = 12.5
  dimension "d24" = 1.2
  dimension "d25" = 4
  dimension "d26" = 11.95
  dimension "d27" = 17.5
  dimension "d28" = 120
  dimension "d29" = 21
  dimension "d33" = 11.95
  dimension "d34" = 12.5
  dimension "d35" = 50
  dimension "d36" = 1.2
  constraint coincident L0.start L24.start
  constraint vertical L0
  constraint perpendicular L1 L2
  constraint perpendicular L2 L3
  constraint perpendicular L3 L4
  constraint perpendicular L2 L5
  constraint perpendicular L5 L6
  constraint perpendicular L6 L7
  constraint perpendicular L7 L8
  constraint perpendicular L8 L9
  constraint perpendicular L7 L10
  constraint perpendicular L10 L11
  constraint perpendicular L11 L12
  constraint horizontal L13
  constraint collinear L2 L6
  constraint collinear L6 L10
  constraint collinear L4 L8
  constraint perpendicular L12 L14
  constraint perpendicular L14 L15
  constraint perpendicular L15 L16
  constraint perpendicular L16 L17
  constraint coincident L13 L18.end
  constraint perpendicular L13 L18
  constraint collinear L12 L17
  constraint perpendicular L1 L19
  constraint perpendicular L0 L20
  constraint perpendicular L20 L21
  constraint perpendicular L21 L22
  constraint perpendicular L22 L23
  constraint collinear L19 L20
  measures "d11" distance of L1.end L2.end
  measures "d12" distance of L3.end L4.end
  measures "d13" distance of L5.end L6.end
  measures "d14" distance of L7.end L8.end
  measures "d15" distance of L9.end L10.end
  measures "d16" distance of L11.end L12.end
  measures "d22" distance of L4 L13
  measures "d23" distance of L12 L13
  measures "d24" distance of L14.end L15.end
  measures "d25" distance of L16.end L17.end
  measures "d26" distance of L13 L15
  measures "d27" distance of L6 L13
  measures "d28" distance of L1.end L10.end
  measures "d29" distance of L1.start L19.start
  measures "d33" distance of L13 L22
  measures "d34" distance of L13 L20
  measures "d35" distance of L0.end L20.end
  measures "d36" distance of L21.end L22.end
revolve "Revolve1" add sketch "Sketch1" angle 360 about axis through (0, 0, 0) along (1, 0, 0)
ref_plane "WorkPlane1" through (87.2, 0, 0) normal (-1, 0, 0) x (0, 0, 1)
sketch "Sketch3" plane through (87.2, 0, 0) normal (-1, 0, 0) x (0, -1, 0)
  line L0 (0, -3) -> (0, 22) construction
  line L1 (-1.4224, 16.258) -> (-1.5252, 17.4334)
  line L2 (1.4224, 16.258) -> (1.5252, 17.4334)
  arc A0 (0.9988, 15.8936) -> (-0.9988, 15.8936) centre (0, 0) ccw
  arc A1 (1.5252, 17.4334) -> (-1.5252, 17.4334) centre (0, 0) ccw
  arc A2 (-1.4224, 16.258) -> (-0.9988, 15.8936) centre (-1.0239, 16.2929) ccw
  arc A3 (0.9988, 15.8936) -> (1.4224, 16.258) centre (1.0239, 16.2929) ccw
  dimension "d43" = 35
  dimension "d44" = 31.85
  dimension "d45" = 5
  dimension "d46" = 0.4
  constraint coincident A0.centre A1.centre
  constraint vertical L0
  constraint symmetric L0 L1.end L2.end
  constraint tangent L1 A2
  constraint tangent A0 A2
  constraint tangent L2 A3
  constraint tangent A0 A3
  constraint equal A2 A3
  measures "d43" diameter of A1
  measures "d44" diameter of A0
  measures "d45" angle of L0 L1
  measures "d46" radius of A2
extrude "Extrude1" cut sketch "Sketch3" against normal blind 50
pattern_circular "C-Pattern1" count 18 over 360 about axis through (72.2, 0, 0) along (1, 0, 0) of "Extrude1"
extrude "Extrude2" add 1 faces at (0, -3.4427, 3.3209) along direction (-1, 0, 0) blind 50

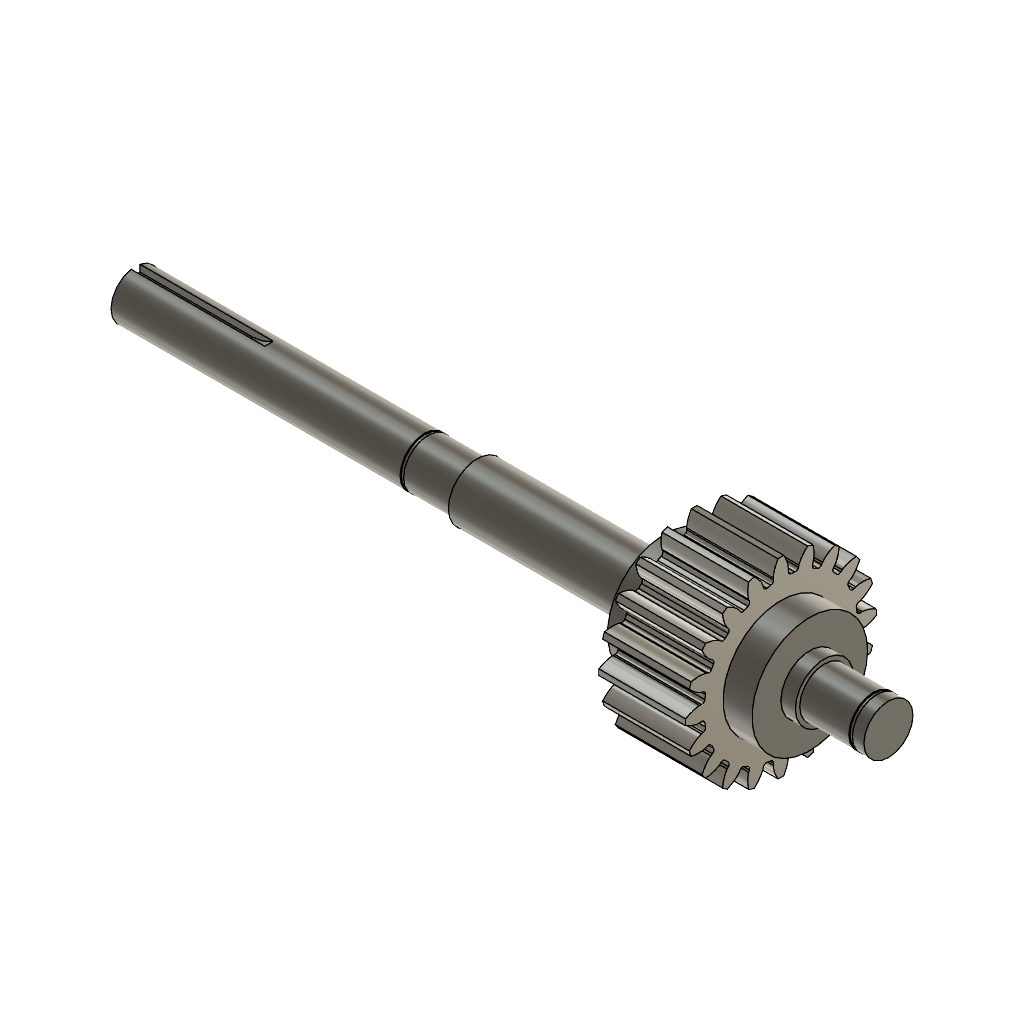
design "input_shaft_assembly"
part number: 2026-10-06-21-04-13-367
Autodesk Fusion 360 part; units mm, degrees
sketch "Sketch1" plane through (0, 0, 0) normal (0, 0, 1) x (1, 0, 0)
  line L0 (68.2, 8.5) -> (68.2, 10)
  line L1 (133.2, 10) -> (133.2, 20)
  line L2 (205.2, 8.5) -> (205.2, 8.1)
  line L3 (51.2, 8.1) -> (51.2, 8.5)
  line L4 (0, 8.5) -> (0, 0)
  line L5 (206.4, 8.5) -> (210.4, 8.5)
  line L6 (0, 8.5) -> (50, 8.5)
  line L7 (173.2, 10) -> (173.2, 20)
  line L8 (51.2, 8.5) -> (68.2, 8.5)
  line L9 (133.2, 20) -> (143.2, 20)
  line L10 (188.2, 10) -> (188.2, 8.5)
  line L11 (173.2, 20) -> (183.2, 20)
  line L12 (143.2, 20) -> (143.2, 10)
  line L13 (183.2, 10) -> (188.2, 10)
  line L14 (188.2, 8.5) -> (205.2, 8.5)
  line L15 (210.4, 8.5) -> (210.4, 0)
  line L16 (183.2, 20) -> (183.2, 10)
  line L17 (206.4, 8.1) -> (206.4, 8.5)
  line L18 (205.2, 8.1) -> (206.4, 8.1)
  line L19 (50, 8.1) -> (51.2, 8.1)
  line L20 (50, 8.5) -> (50, 8.1)
  line L21 (68.2, 10) -> (133.2, 10)
  line L22 (0, 0) -> (210.4, 0)
  line L23 (143.2, 10) -> (173.2, 10)
  dimension "d1" = 10
  dimension "d2" = 30
  dimension "d3" = 10
  dimension "d4" = 1.2
  dimension "d5" = 4
  dimension "d6" = 65
  dimension "d7" = 5
  dimension "d8" = 17
  dimension "d9" = 77.2
  dimension "d10" = 120
  dimension "d11" = 1.2
  dimension "d12" = 17
  dimension "d13" = 50
  constraint coincident L4.end L22.start
  constraint perpendicular L1 L9
  constraint perpendicular L9 L12
  constraint perpendicular L12 L23
  constraint perpendicular L7 L23
  constraint perpendicular L7 L11
  constraint perpendicular L16 L23
  constraint perpendicular L2 L18
  constraint perpendicular L17 L18
  constraint perpendicular L2 L5
  constraint perpendicular L5 L15
  constraint perpendicular L1 L21
  constraint perpendicular L4 L21
  constraint vertical L4
  constraint perpendicular L13 L16
  constraint perpendicular L10 L13
  constraint perpendicular L2 L14
  constraint collinear L9 L11
  constraint perpendicular L4 L6
  constraint perpendicular L6 L20
  constraint collinear L6 L8
  constraint collinear L5 L14
  constraint horizontal L19
  constraint perpendicular L15 L22
  measures "d1" distance of L9.end L1.end
  measures "d2" distance of L12.end L7.start
  measures "d3" distance of L11.end L7.end
  measures "d4" distance of L2.end L17.start
  measures "d5" distance of L5.end L5.start
  measures "d6" distance of L0.end L1.start
  measures "d7" distance of L13.start L10.start
  measures "d8" distance of L2.start L10.end
  measures "d9" horizontal distance of L5.end L1.end
  measures "d10" distance of L0.end L10.start
  measures "d11" distance of L3.start L19.start
  measures "d12" distance of L0.start L3.end
  measures "d13" distance of L6.end L4.start
revolve "Revolve1" add sketch "Sketch1" angle 360 about axis through (0, 0, 0) along (1, 0, 0) makes body 1
sketch "Base Circle" plane through (0, 0, 0) normal (0, 0, 1) x (1, 0, 0)
  circle A0 centre (0, 0) radius 26.529
  circle A1 centre (0, 0) radius 10
extrude "Extrude1" add sketch "Base Circle" along normal blind 30 separate body makes body 2
sketch "Gear Tooth" plane through (0, 0, 0) normal (0, 0, 1) x (1, 0, 0)
  spline S0 degree 5 poles (28.0704, -2.6024) (28.0845, -2.6037) (28.1128, -2.6059) (28.1553, -2.6081) (28.2119, -2.609) (28.2829, -2.6071) (28.3539, -2.603) (28.425, -2.5977) (28.4961, -2.5916) (28.5673, -2.5851) (28.6385, -2.5781) (28.7097, -2.5704) (28.7808, -2.5618) (28.852, -2.5522) (28.9232, -2.5416) (28.9945, -2.53) (29.0657, -2.5176) (29.1368, -2.5046) (29.208, -2.4909) (29.2792, -2.4767) (29.3503, -2.4619) (29.4214, -2.4465) (29.4925, -2.4305) (29.5636, -2.4138) (29.6347, -2.3965) (29.7057, -2.3786) (29.7767, -2.3601) (29.8476, -2.3411) (29.9185, -2.3215) (29.9894, -2.3015) (30.0603, -2.2809) (30.1311, -2.2598) (30.2019, -2.2381) (30.2726, -2.216) (30.3433, -2.1934) (30.4139, -2.1702) (30.4845, -2.1466) (30.5551, -2.1225) (30.6256, -2.0979) (30.696, -2.0728) (30.7664, -2.0473) (30.8368, -2.0214) (30.907, -1.995) (30.9773, -1.9681) (31.0475, -1.9408) (31.1176, -1.913) (31.1876, -1.8848) (31.2576, -1.8562) (31.3276, -1.8271) (31.3974, -1.7976) (31.4672, -1.7677) (31.537, -1.7374) (31.6067, -1.7067) (31.6763, -1.6755) (31.7458, -1.6439) (31.8153, -1.612) (31.8847, -1.5796) (31.954, -1.5469) (32.0233, -1.5137) (32.0924, -1.4801) (32.1615, -1.4462) (32.2306, -1.4119) (32.2995, -1.3771) (32.3684, -1.342) (32.4372, -1.3065) (32.5059, -1.2707) (32.5745, -1.2344) (32.6431, -1.1978) (32.7116, -1.1609) (32.7799, -1.1235) (32.8482, -1.0858) (32.9028, -1.0553) (32.9437, -1.0323) (32.9709, -1.0169) (32.9846, -1.0092) knots 0 0 0 0 0 0 0.01428571 0.02857143 0.04285714 0.05714286 0.07142857 0.08571429 0.1 0.11428571 0.12857143 0.14285714 0.15714286 0.17142857 0.18571429 0.2 0.21428571 0.22857143 0.24285714 0.25714286 0.27142857 0.28571429 0.3 0.31428571 0.32857143 0.34285714 0.35714286 0.37142857 0.38571429 0.4 0.41428571 0.42857143 0.44285714 0.45714286 0.47142857 0.48571429 0.5 0.51428571 0.52857143 0.54285714 0.55714286 0.57142857 0.58571429 0.6 0.61428571 0.62857143 0.64285714 0.65714286 0.67142857 0.68571429 0.7 0.71428571 0.72857143 0.74285714 0.75714286 0.77142857 0.78571429 0.8 0.81428571 0.82857143 0.84285714 0.85714286 0.87142857 0.88571429 0.9 0.91428571 0.92857143 0.94285714 0.95714286 0.97142857 0.98571429 1 1 1 1 1 1
  spline S1 degree 5 poles (28.0704, 2.6024) (28.0845, 2.6037) (28.1128, 2.6059) (28.1553, 2.6081) (28.2119, 2.609) (28.2829, 2.6071) (28.3539, 2.603) (28.425, 2.5977) (28.4961, 2.5916) (28.5673, 2.5851) (28.6385, 2.5781) (28.7097, 2.5704) (28.7808, 2.5618) (28.852, 2.5522) (28.9232, 2.5416) (28.9945, 2.53) (29.0657, 2.5176) (29.1368, 2.5046) (29.208, 2.4909) (29.2792, 2.4767) (29.3503, 2.4619) (29.4214, 2.4465) (29.4925, 2.4305) (29.5636, 2.4138) (29.6347, 2.3965) (29.7057, 2.3786) (29.7767, 2.3601) (29.8476, 2.3411) (29.9185, 2.3215) (29.9894, 2.3015) (30.0603, 2.2809) (30.1311, 2.2598) (30.2019, 2.2381) (30.2726, 2.216) (30.3433, 2.1934) (30.4139, 2.1702) (30.4845, 2.1466) (30.5551, 2.1225) (30.6256, 2.0979) (30.696, 2.0728) (30.7664, 2.0473) (30.8368, 2.0214) (30.907, 1.995) (30.9773, 1.9681) (31.0475, 1.9408) (31.1176, 1.913) (31.1876, 1.8848) (31.2576, 1.8562) (31.3276, 1.8271) (31.3974, 1.7976) (31.4672, 1.7677) (31.537, 1.7374) (31.6067, 1.7067) (31.6763, 1.6755) (31.7458, 1.6439) (31.8153, 1.612) (31.8847, 1.5796) (31.954, 1.5469) (32.0233, 1.5137) (32.0924, 1.4801) (32.1615, 1.4462) (32.2306, 1.4119) (32.2995, 1.3771) (32.3684, 1.342) (32.4372, 1.3065) (32.5059, 1.2707) (32.5745, 1.2344) (32.6431, 1.1978) (32.7116, 1.1609) (32.7799, 1.1235) (32.8482, 1.0858) (32.9028, 1.0553) (32.9437, 1.0323) (32.9709, 1.0169) (32.9846, 1.0092) knots 0 0 0 0 0 0 0.01428571 0.02857143 0.04285714 0.05714286 0.07142857 0.08571429 0.1 0.11428571 0.12857143 0.14285714 0.15714286 0.17142857 0.18571429 0.2 0.21428571 0.22857143 0.24285714 0.25714286 0.27142857 0.28571429 0.3 0.31428571 0.32857143 0.34285714 0.35714286 0.37142857 0.38571429 0.4 0.41428571 0.42857143 0.44285714 0.45714286 0.47142857 0.48571429 0.5 0.51428571 0.52857143 0.54285714 0.55714286 0.57142857 0.58571429 0.6 0.61428571 0.62857143 0.64285714 0.65714286 0.67142857 0.68571429 0.7 0.71428571 0.72857143 0.74285714 0.75714286 0.77142857 0.78571429 0.8 0.81428571 0.82857143 0.84285714 0.85714286 0.87142857 0.88571429 0.9 0.91428571 0.92857143 0.94285714 0.95714286 0.97142857 0.98571429 1 1 1 1 1 1
  arc A0 (32.9846, -1.0092) -> (32.9846, 1.0092) centre (0, 0) ccw
  line L0 (26.4058, -2.448) -> (28.0704, -2.6024)
  line L1 (26.4058, 2.448) -> (28.0704, 2.6024)
  line L2 (26.4058, -2.448) -> (26.4058, 2.448)
  point P0 (28.4158, -2.5982)
  point P1 (28.7638, -2.5637)
  point P2 (29.1134, -2.5088)
  point P3 (29.4643, -2.4367)
  point P4 (29.8159, -2.3495)
  point P5 (30.1682, -2.2484)
  point P6 (30.5209, -2.1341)
  point P7 (30.8737, -2.0074)
  point P8 (31.2265, -1.8688)
  point P9 (31.5792, -1.7187)
  point P10 (31.9315, -1.5574)
  point P11 (32.2833, -1.3853)
  point P12 (32.6343, -1.2024)
  point P13 (28.4158, 2.5982)
  point P14 (28.7638, 2.5637)
  point P15 (29.1134, 2.5088)
  point P16 (29.4643, 2.4367)
  point P17 (29.8159, 2.3495)
  point P18 (30.1682, 2.2484)
  point P19 (30.5209, 2.1341)
  point P20 (30.8737, 2.0074)
  point P21 (31.2265, 1.8688)
  point P22 (31.5792, 1.7187)
  point P23 (31.9315, 1.5574)
  point P24 (32.2833, 1.3853)
  point P25 (32.6343, 1.2024)
extrude "Extrude2" add sketch "Gear Tooth" along normal blind 30 bodies 2
fillet "Fillet1" radius 1.05 2 edges at (26.4157, -2.449, 15) (26.4157, 2.449, 15) on bodies 2
pattern_circular "C-Pattern1" count 20 over 360 about axis through (0, 0, 0) along (0, 0, 1) of "Extrude2", "Fillet1"
sketch "Diametrial Pitch Circle" plane through (0, 0, 0) normal (0, 0, 1) x (1, 0, 0)
  circle A0 centre (0, 0) radius 30 construction
move_body "Move1" bodies 2 to x (0, 0, -1) y (0, 1, 0) z (1, 0, 0) at (0, 0, 0)
move_body "Align1" bodies 2 to x (1, 0, 0) y (0, 1, 0) z (0, 0, 1) at (143.2, 0, 0)
extrude "Extrude3" add 1 faces at (0, -2.3259, -3.5788) along direction (-1, 0, 0) blind 50 on bodies 1 bodies 1
sketch "Sketch5" plane through (0, 0, 0) normal (0, 1, 0) x (1, 0, 0)
  line L0 (-51, -6) -> (-11, -6)
  spline S0 degree 5 poles (-11, -6) (-10.834, -6.0062) (-10.5016, -6.0239) (-10.002, -6.0664) (-9.3339, -6.1557) (-8.4952, -6.3251) (-7.6526, -6.5571) (-6.8059, -6.8561) (-5.9549, -7.2235) (-5.0999, -7.6552) (-4.2413, -8.146) (-3.5517, -8.5818) (-3.0331, -8.9312) (-2.6868, -9.1741) (-2.5135, -9.298) knots 0 0 0 0 0 0 0.1 0.2 0.3 0.4 0.5 0.6 0.7 0.8 0.9 1 1 1 1 1 1
  line L1 (-2.5135, -9.298) -> (-51, -9.298)
  line L2 (-51, -9.298) -> (-51, -6)
  point P0 (-7.0028, -6.7973)
  constraint horizontal L0
  constraint horizontal L1
  constraint perpendicular L0 L2
extrude "Extrude4" cut sketch "Sketch5" along normal mid plane 3 bodies 1
